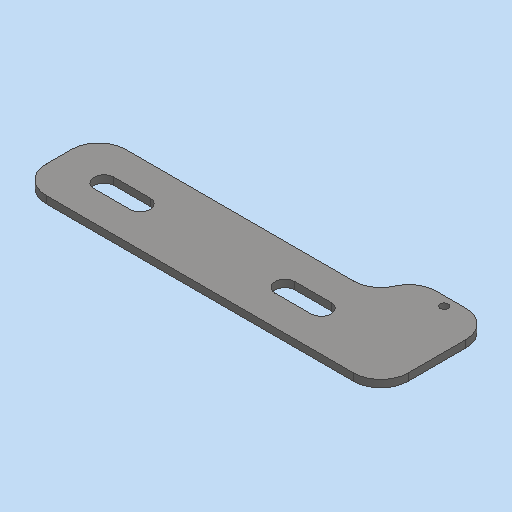
# Autodesk Inventor part: SE0004AN000_G01_108
Saved by Autodesk Inventor 2023.3 (Build 273359000, 359)
## iProperties
RuleStatus: InUse
Created: 2021-07-09
Part Number: SE0004AN000_G01_108
Material: 1.4301 X5CrNi18-10
Description: =<RBPARTNOTITLE2>
Document SubType Name: Blech
Designer: frt9bw
Mass: 275.548 g
Surface Area: 201.54 cm^2
Volume: 35.1017 cm^3
Density: 7.85 g/cm^3
Sheet Metal Rule: Standard_mm
Appearance: Stahl - rostfrei AnP
Vendor: ASW
AnP_Kategorie: 1
AnP_Material: =<Material>
MaxAbmaße: 4 x 62 x 200 (FM)
AnP_TemplVers: 20200821
RBDOCUMENTTYPE: DRF
RBDOCUMENTVERSION: 00
RBDRAWINGMAINSCALE: 1:1
RBDRAWINGMISSINGSPEC: --
RBDRAWINGVOLUME: --
RBDSV1: 0850
RBGBEDGESIN1: +0,5
RBGBEDGESIN2: +0,2
RBGBEDGESOUT1: -0,3
RBGBEDGESOUT2: -0,1
RBMATERIAL: =<Material>
RBMATMEETS: --
RBMATNO: =<Part Number>
RBPARTMADEOF: 4 x 62 x 200 (FM)
RBPARTNO: SIEHE MNR
RBPARTNOTITLE1: manufactured part
RBPARTNOTITLE2: Anfertigungsteil
RBPARTSAFETYINDICATOR: --
RBSURFACE: --
RBSURFACE2: --
RBZEDGESNORM: ISO13715:2002-06
RBZGENDIMCLASS: m
RBZGENDIMNORM: ISO 2768-1:1989-11
RBZGENGEOCLASS: H
RBZGENGEONORM: ISO 2768-2:1989-11
RBZSURFACENORM: ISO13D2:2002-02
RBZTOLERANCENORM: ISO 14405-1:2010-12
Author: frt9bw
Keywords: =<RBPARTMADEOF>
Comments: =<RBSURFACE2>
Revision Number: 01
Autodesk Inventor part; units mm, degrees
ref_plane "YZ Plane" through (0, 0, 0) normal (1, 0, 0) x (0, 1, 0)
ref_plane "XZ Plane" through (0, 0, 0) normal (0, 1, 0) x (-1, 0, 0)
ref_plane "XY Plane" through (0, 0, 0) normal (0, 0, 1) x (1, 0, 0)
sketch "Skizze1" plane through (0, 0, 0) normal (0, 0, 1) x (1, 0, 0)
  line L0 (0, 0) -> (200, 0)
  line L1 (200, 0) -> (200, 62)
  line L2 (200, 62) -> (0, 62)
  line L3 (0, 62) -> (0, 0)
  dimension "d0" = 200
  dimension "d1" = 62
  measures "d0" distance of L2.end L1.end
  measures "d1" distance of L1.end L0.end
extrude "Grobblech1" add sketch "Skizze1" along normal blind 4
sketch "Skizze2" plane through (0, 0, 4) normal (0, 0, 1) x (1, 0, 0)
  line L0 (0, 0) -> (0, 62) projected
  line L1 (200, 0) -> (0, 0) projected
  line L2 (200, 62) -> (200, 0) projected
  line L3 (0, 62) -> (200, 62) projected
  line L4 (0, 62) -> (156, 62)
  line L5 (156, 62) -> (156, 44)
  line L6 (156, 44) -> (0, 44)
  line L7 (0, 44) -> (0, 62)
  point P0 (0, 44)
  dimension "d3" = 44
  dimension "d4" = 44
  constraints: 8 end point, 2 parallel, 1 horizontal, 1 perpendicular
  measures "d3" distance between parallel lines of L1 L6
  measures "d4" distance between parallel lines of L2 L5
extrude "Extrusion1" cut sketch "Skizze2" against normal blind 10 contours L0 L3 L5 L6
sketch "Skizze3" plane through (0, 0, 4) normal (0, 0, 1) x (1, 0, 0)
  line L0 (200, 62) -> (200, 0) projected
  line L1 (156, 62) -> (200, 62) projected
  point P0 (0, 0)
  point P1 (178, 57)
  dimension "d7" = 22
  dimension "d8" = 5
  measures "d7" distance from line of L0 point (178, 57)
  measures "d8" distance from line of L1 point (178, 57)
hole "Bohrung1" at (178, 57, 4) direction (0, 0, -1) diameter 4.5 end through all
fillet "Rundung1" radius 15 6 edges at (0, 0, 2) (200, 0, 2) (200, 62, 2) (156, 62, 2) (156, 44, 2) (0, 44, 2)
sketch "Skizze4" plane through (0, 0, 4) normal (0, 0, 1) x (1, 0, 0)
  arc A0 (168.4955, 62) -> (154.7477, 53) centre (168.4955, 47) ccw projected
  arc A1 (141, 44) -> (154.7477, 53) centre (141, 59) ccw projected
  line L0 (141, 44) -> (15, 44) projected
  arc A2 (15, 44) -> (0, 29) centre (15, 29) ccw projected
  line L1 (0, 15) -> (0, 29) projected
  arc A3 (0, 15) -> (15, 0) centre (15, 15) ccw projected
  line L2 (185, 0) -> (15, 0) projected
  arc A4 (185, 0) -> (200, 15) centre (185, 15) ccw projected
  line L3 (200, 47) -> (200, 15) projected
  arc A5 (200, 47) -> (185, 62) centre (185, 47) ccw projected
  line L4 (168.4955, 62) -> (185, 62) projected
  circle A6 centre (178, 57) radius 2.25 projected
  line L5 (25, 22) -> (45, 22) construction
  line L6 (25, 16.5) -> (45, 16.5)
  line L7 (45, 27.5) -> (25, 27.5)
  arc A7 (25, 27.5) -> (25, 16.5) centre (25, 22) ccw
  arc A8 (45, 16.5) -> (45, 27.5) centre (45, 22) ccw
  line L8 (125, 22) -> (145, 22) construction
  line L9 (125, 16.5) -> (145, 16.5)
  line L10 (145, 27.5) -> (125, 27.5)
  arc A9 (125, 27.5) -> (125, 16.5) centre (125, 22) ccw
  arc A10 (145, 16.5) -> (145, 27.5) centre (145, 22) ccw
  point P0 (0, 0)
  point P1 (35, 22)
  point P2 (135, 22)
  dimension "d17" = 11
  dimension "d18" = 11
  dimension "d19" = 35
  dimension "d20" = 100
  dimension "d21" = 22
  dimension "d22" = 20
  dimension "d23" = 20
  constraints: 16 end point, 8 point on circle, 8 tangent, 4 centre point, 2 midpoint, 2 parallel, 2 point on line, 1 horizontal, 1 horizontal alignment
  measures "d17" diameter of A8
  measures "d18" diameter of A10
  measures "d19" distance from line of L1 point (35, 22)
  measures "d20" distance of point (135, 22) point (35, 22)
  measures "d21" distance from line of point (35, 22) L2
  measures "d22" distance of L5.end L5.start
  measures "d23" distance of L8.end L8.start
extrude "Extrusion2" cut sketch "Skizze4" against normal through all contours A7 L7 A8 L6 | A9 L10 A10 L9
equation "\"d14\" = Stärke"
equation "\"d2\" = Stärke"
equation "\"Biegeradius\" = Stärke"
equation "\"BreiteBiegungsfreistellung\" = Stärke"
equation "\"TiefeBiegungsfreistellung\" = 0.5 * Stärke"
equation "\"GrößeEckenfreistellung\" = 4 * Stärke"
equation "\"MinimalRest\" = 2 * Stärke"
equation "\"Übergangsradius\" = Biegeradius"
equation "\"JacobiRadiusGröße\" = Biegeradius"
equation "\"Abstandsgröße\" = Stärke"
equation "\"Stärke\" = 4"
